Autodesk Fusion 360 part; units mm, degrees
(part 3 of 3)
extrude "Label 4.5 dot" cut sketch "Label 4.5 dot sketch" along normal blind 1 bodies 10 in component "07 Spar fit coupon - 4.1 4.3 4.4 4.5 4.7"
ref_plane "WorkPlane36" through (0, 0, 9.4) normal (0, 0, 1) x (1, 0, 0) in component "07 Spar fit coupon - 4.1 4.3 4.4 4.5 4.7"
sketch "Label 4.5 digit 2 a sketch" plane through (0, 0, 9.4) normal (0, 0, 1) x (1, 0, 0) in component "07 Spar fit coupon - 4.1 4.3 4.4 4.5 4.7"
  line L0 (13, 43.2) -> (14.8, 43.2)
  line L1 (14.8, 43.2) -> (14.8, 43.5)
  line L2 (14.8, 43.5) -> (13, 43.5)
  line L3 (13, 43.5) -> (13, 43.2)
extrude "Label 4.5 digit 2 a" cut sketch "Label 4.5 digit 2 a sketch" along normal blind 1 bodies 10 in component "07 Spar fit coupon - 4.1 4.3 4.4 4.5 4.7"
ref_plane "WorkPlane37" through (0, 0, 9.4) normal (0, 0, 1) x (1, 0, 0) in component "07 Spar fit coupon - 4.1 4.3 4.4 4.5 4.7"
sketch "Label 4.5 digit 2 f sketch" plane through (0, 0, 9.4) normal (0, 0, 1) x (1, 0, 0) in component "07 Spar fit coupon - 4.1 4.3 4.4 4.5 4.7"
  line L0 (13, 42.15) -> (13.3, 42.15)
  line L1 (13.3, 42.15) -> (13.3, 43.05)
  line L2 (13.3, 43.05) -> (13, 43.05)
  line L3 (13, 43.05) -> (13, 42.15)
extrude "Label 4.5 digit 2 f" cut sketch "Label 4.5 digit 2 f sketch" along normal blind 1 bodies 10 in component "07 Spar fit coupon - 4.1 4.3 4.4 4.5 4.7"
ref_plane "WorkPlane38" through (0, 0, 9.4) normal (0, 0, 1) x (1, 0, 0) in component "07 Spar fit coupon - 4.1 4.3 4.4 4.5 4.7"
sketch "Label 4.5 digit 2 g sketch" plane through (0, 0, 9.4) normal (0, 0, 1) x (1, 0, 0) in component "07 Spar fit coupon - 4.1 4.3 4.4 4.5 4.7"
  line L0 (13, 41.85) -> (14.8, 41.85)
  line L1 (14.8, 41.85) -> (14.8, 42.15)
  line L2 (14.8, 42.15) -> (13, 42.15)
  line L3 (13, 42.15) -> (13, 41.85)
extrude "Label 4.5 digit 2 g" cut sketch "Label 4.5 digit 2 g sketch" along normal blind 1 bodies 10 in component "07 Spar fit coupon - 4.1 4.3 4.4 4.5 4.7"
ref_plane "WorkPlane39" through (0, 0, 9.4) normal (0, 0, 1) x (1, 0, 0) in component "07 Spar fit coupon - 4.1 4.3 4.4 4.5 4.7"
sketch "Label 4.5 digit 2 c sketch" plane through (0, 0, 9.4) normal (0, 0, 1) x (1, 0, 0) in component "07 Spar fit coupon - 4.1 4.3 4.4 4.5 4.7"
  line L0 (14.5, 40.95) -> (14.8, 40.95)
  line L1 (14.8, 40.95) -> (14.8, 41.85)
  line L2 (14.8, 41.85) -> (14.5, 41.85)
  line L3 (14.5, 41.85) -> (14.5, 40.95)
extrude "Label 4.5 digit 2 c" cut sketch "Label 4.5 digit 2 c sketch" along normal blind 1 bodies 10 in component "07 Spar fit coupon - 4.1 4.3 4.4 4.5 4.7"
ref_plane "WorkPlane40" through (0, 0, 9.4) normal (0, 0, 1) x (1, 0, 0) in component "07 Spar fit coupon - 4.1 4.3 4.4 4.5 4.7"
sketch "Label 4.5 digit 2 d sketch" plane through (0, 0, 9.4) normal (0, 0, 1) x (1, 0, 0) in component "07 Spar fit coupon - 4.1 4.3 4.4 4.5 4.7"
  line L0 (13, 40.5) -> (14.8, 40.5)
  line L1 (14.8, 40.5) -> (14.8, 40.8)
  line L2 (14.8, 40.8) -> (13, 40.8)
  line L3 (13, 40.8) -> (13, 40.5)
extrude "Label 4.5 digit 2 d" cut sketch "Label 4.5 digit 2 d sketch" along normal blind 1 bodies 10 in component "07 Spar fit coupon - 4.1 4.3 4.4 4.5 4.7"
ref_plane "WorkPlane41" through (-0.05, 0, 0) normal (1, 0, 0) x (0, 1, 0) in component "07 Spar fit coupon - 4.1 4.3 4.4 4.5 4.7"
sketch "Diamond 4.7 mm flat-width fit bore sketch" plane through (-0.05, 0, 0) normal (1, 0, 0) x (0, 0, -1) in component "07 Spar fit coupon - 4.1 4.3 4.4 4.5 4.7"
  line L0 (-4.5, 50.6766) -> (-1.1766, 54)
  line L1 (-1.1766, 54) -> (-4.5, 57.3234)
  line L2 (-4.5, 57.3234) -> (-7.8234, 54)
  line L3 (-7.8234, 54) -> (-4.5, 50.6766)
extrude "Diamond 4.7 mm flat-width fit bore" cut sketch "Diamond 4.7 mm flat-width fit bore sketch" along normal blind 24.1 bodies 10 in component "07 Spar fit coupon - 4.1 4.3 4.4 4.5 4.7"
ref_plane "WorkPlane42" through (0, 0, 9.4) normal (0, 0, 1) x (1, 0, 0) in component "07 Spar fit coupon - 4.1 4.3 4.4 4.5 4.7"
sketch "Label 4.7 digit 0 f sketch" plane through (0, 0, 9.4) normal (0, 0, 1) x (1, 0, 0) in component "07 Spar fit coupon - 4.1 4.3 4.4 4.5 4.7"
  line L0 (8, 54.15) -> (8.3, 54.15)
  line L1 (8.3, 54.15) -> (8.3, 55.05)
  line L2 (8.3, 55.05) -> (8, 55.05)
  line L3 (8, 55.05) -> (8, 54.15)
extrude "Label 4.7 digit 0 f" cut sketch "Label 4.7 digit 0 f sketch" along normal blind 1 bodies 10 in component "07 Spar fit coupon - 4.1 4.3 4.4 4.5 4.7"
ref_plane "WorkPlane43" through (0, 0, 9.4) normal (0, 0, 1) x (1, 0, 0) in component "07 Spar fit coupon - 4.1 4.3 4.4 4.5 4.7"
sketch "Label 4.7 digit 0 g sketch" plane through (0, 0, 9.4) normal (0, 0, 1) x (1, 0, 0) in component "07 Spar fit coupon - 4.1 4.3 4.4 4.5 4.7"
  line L0 (8, 53.85) -> (9.8, 53.85)
  line L1 (9.8, 53.85) -> (9.8, 54.15)
  line L2 (9.8, 54.15) -> (8, 54.15)
  line L3 (8, 54.15) -> (8, 53.85)
extrude "Label 4.7 digit 0 g" cut sketch "Label 4.7 digit 0 g sketch" along normal blind 1 bodies 10 in component "07 Spar fit coupon - 4.1 4.3 4.4 4.5 4.7"
ref_plane "WorkPlane44" through (0, 0, 9.4) normal (0, 0, 1) x (1, 0, 0) in component "07 Spar fit coupon - 4.1 4.3 4.4 4.5 4.7"
sketch "Label 4.7 digit 0 b sketch" plane through (0, 0, 9.4) normal (0, 0, 1) x (1, 0, 0) in component "07 Spar fit coupon - 4.1 4.3 4.4 4.5 4.7"
  line L0 (9.5, 54.15) -> (9.8, 54.15)
  line L1 (9.8, 54.15) -> (9.8, 55.05)
  line L2 (9.8, 55.05) -> (9.5, 55.05)
  line L3 (9.5, 55.05) -> (9.5, 54.15)
extrude "Label 4.7 digit 0 b" cut sketch "Label 4.7 digit 0 b sketch" along normal blind 1 bodies 10 in component "07 Spar fit coupon - 4.1 4.3 4.4 4.5 4.7"
ref_plane "WorkPlane45" through (0, 0, 9.4) normal (0, 0, 1) x (1, 0, 0) in component "07 Spar fit coupon - 4.1 4.3 4.4 4.5 4.7"
sketch "Label 4.7 digit 0 c sketch" plane through (0, 0, 9.4) normal (0, 0, 1) x (1, 0, 0) in component "07 Spar fit coupon - 4.1 4.3 4.4 4.5 4.7"
  line L0 (9.5, 52.95) -> (9.8, 52.95)
  line L1 (9.8, 52.95) -> (9.8, 53.85)
  line L2 (9.8, 53.85) -> (9.5, 53.85)
  line L3 (9.5, 53.85) -> (9.5, 52.95)
extrude "Label 4.7 digit 0 c" cut sketch "Label 4.7 digit 0 c sketch" along normal blind 1 bodies 10 in component "07 Spar fit coupon - 4.1 4.3 4.4 4.5 4.7"
ref_plane "WorkPlane46" through (0, 0, 9.4) normal (0, 0, 1) x (1, 0, 0) in component "07 Spar fit coupon - 4.1 4.3 4.4 4.5 4.7"
sketch "Label 4.7 dot sketch" plane through (0, 0, 9.4) normal (0, 0, 1) x (1, 0, 0) in component "07 Spar fit coupon - 4.1 4.3 4.4 4.5 4.7"
  line L0 (10.5, 52.5) -> (10.85, 52.5)
  line L1 (10.85, 52.5) -> (10.85, 52.85)
  line L2 (10.85, 52.85) -> (10.5, 52.85)
  line L3 (10.5, 52.85) -> (10.5, 52.5)
extrude "Label 4.7 dot" cut sketch "Label 4.7 dot sketch" along normal blind 1 bodies 10 in component "07 Spar fit coupon - 4.1 4.3 4.4 4.5 4.7"
ref_plane "WorkPlane47" through (0, 0, 9.4) normal (0, 0, 1) x (1, 0, 0) in component "07 Spar fit coupon - 4.1 4.3 4.4 4.5 4.7"
sketch "Label 4.7 digit 2 a sketch" plane through (0, 0, 9.4) normal (0, 0, 1) x (1, 0, 0) in component "07 Spar fit coupon - 4.1 4.3 4.4 4.5 4.7"
  line L0 (13, 55.2) -> (14.8, 55.2)
  line L1 (14.8, 55.2) -> (14.8, 55.5)
  line L2 (14.8, 55.5) -> (13, 55.5)
  line L3 (13, 55.5) -> (13, 55.2)
extrude "Label 4.7 digit 2 a" cut sketch "Label 4.7 digit 2 a sketch" along normal blind 1 bodies 10 in component "07 Spar fit coupon - 4.1 4.3 4.4 4.5 4.7"
ref_plane "WorkPlane48" through (0, 0, 9.4) normal (0, 0, 1) x (1, 0, 0) in component "07 Spar fit coupon - 4.1 4.3 4.4 4.5 4.7"
sketch "Label 4.7 digit 2 b sketch" plane through (0, 0, 9.4) normal (0, 0, 1) x (1, 0, 0) in component "07 Spar fit coupon - 4.1 4.3 4.4 4.5 4.7"
  line L0 (14.5, 54.15) -> (14.8, 54.15)
  line L1 (14.8, 54.15) -> (14.8, 55.05)
  line L2 (14.8, 55.05) -> (14.5, 55.05)
  line L3 (14.5, 55.05) -> (14.5, 54.15)
extrude "Label 4.7 digit 2 b" cut sketch "Label 4.7 digit 2 b sketch" along normal blind 1 bodies 10 in component "07 Spar fit coupon - 4.1 4.3 4.4 4.5 4.7"
ref_plane "WorkPlane49" through (0, 0, 9.4) normal (0, 0, 1) x (1, 0, 0) in component "07 Spar fit coupon - 4.1 4.3 4.4 4.5 4.7"
sketch "Label 4.7 digit 2 c sketch" plane through (0, 0, 9.4) normal (0, 0, 1) x (1, 0, 0) in component "07 Spar fit coupon - 4.1 4.3 4.4 4.5 4.7"
  line L0 (14.5, 52.95) -> (14.8, 52.95)
  line L1 (14.8, 52.95) -> (14.8, 53.85)
  line L2 (14.8, 53.85) -> (14.5, 53.85)
  line L3 (14.5, 53.85) -> (14.5, 52.95)
extrude "Label 4.7 digit 2 c" cut sketch "Label 4.7 digit 2 c sketch" along normal blind 1 bodies 10 in component "07 Spar fit coupon - 4.1 4.3 4.4 4.5 4.7"
ref_plane "WorkPlane1" through (0, 0, 52.7) normal (0, 0, 1) x (1, 0, 0) in component "REFERENCE ONLY - bamboo, example bar cell, sensor envelopes"
sketch "EXAMPLE 60mm bar cell - no assumed screw pattern sketch" plane through (0, 0, 52.7) normal (0, 0, 1) x (1, 0, 0) in component "REFERENCE ONLY - bamboo, example bar cell, sensor envelopes"
  line L0 (368.4, -6.35) -> (428.4, -6.35)
  line L1 (428.4, -6.35) -> (428.4, 6.35)
  line L2 (428.4, 6.35) -> (368.4, 6.35)
  line L3 (368.4, 6.35) -> (368.4, -6.35)
extrude "EXAMPLE 60mm bar cell - no assumed screw pattern" add sketch "EXAMPLE 60mm bar cell - no assumed screw pattern sketch" along normal blind 12.7 separate body makes body 11 in component "REFERENCE ONLY - bamboo, example bar cell, sensor envelopes"
ref_plane "WorkPlane2" through (-6.6, 0, 0) normal (1, 0, 0) x (0, 1, 0) in component "REFERENCE ONLY - bamboo, example bar cell, sensor envelopes"
sketch "4mm bamboo reference -18 sketch" plane through (-6.6, 0, 0) normal (1, 0, 0) x (0, 0, -1) in component "REFERENCE ONLY - bamboo, example bar cell, sensor envelopes"
  circle A0 centre (-20.5, -18) radius 2
extrude "4mm bamboo reference -18" add sketch "4mm bamboo reference -18 sketch" along normal blind 361 separate body makes body 12 in component "REFERENCE ONLY - bamboo, example bar cell, sensor envelopes"
ref_plane "WorkPlane3" through (-6.6, 0, 0) normal (1, 0, 0) x (0, 1, 0) in component "REFERENCE ONLY - bamboo, example bar cell, sensor envelopes"
sketch "4mm bamboo reference 18 sketch" plane through (-6.6, 0, 0) normal (1, 0, 0) x (0, 0, -1) in component "REFERENCE ONLY - bamboo, example bar cell, sensor envelopes"
  circle A0 centre (-20.5, 18) radius 2
extrude "4mm bamboo reference 18" add sketch "4mm bamboo reference 18 sketch" along normal blind 361 separate body makes body 13 in component "REFERENCE ONLY - bamboo, example bar cell, sensor envelopes"
ref_plane "WorkPlane4" through (0, 0, 23.2) normal (0, 0, 1) x (1, 0, 0) in component "REFERENCE ONLY - bamboo, example bar cell, sensor envelopes"
sketch "MPU board envelope sketch" plane through (0, 0, 23.2) normal (0, 0, 1) x (1, 0, 0) in component "REFERENCE ONLY - bamboo, example bar cell, sensor envelopes"
  line L0 (75, -10) -> (97, -10)
  line L1 (97, -10) -> (97, 10)
  line L2 (97, 10) -> (75, 10)
  line L3 (75, 10) -> (75, -10)
extrude "MPU board envelope" add sketch "MPU board envelope sketch" along normal blind 1.6 separate body makes body 14 in component "REFERENCE ONLY - bamboo, example bar cell, sensor envelopes"
ref_plane "WorkPlane5" through (0, 0, 17.8) normal (0, 0, 1) x (1, 0, 0) in component "REFERENCE ONLY - bamboo, example bar cell, sensor envelopes"
sketch "Gauge backing envelope sketch" plane through (0, 0, 17.8) normal (0, 0, 1) x (1, 0, 0) in component "REFERENCE ONLY - bamboo, example bar cell, sensor envelopes"
  line L0 (33, -3) -> (43, -3)
  line L1 (43, -3) -> (43, 3)
  line L2 (43, 3) -> (33, 3)
  line L3 (33, 3) -> (33, -3)
extrude "Gauge backing envelope" add sketch "Gauge backing envelope sketch" along normal blind 0.2 separate body makes body 15 in component "REFERENCE ONLY - bamboo, example bar cell, sensor envelopes"
component "01A Wing root - gauge and MPU" placed x (1, 0, 0) y (0, 1, 0) z (0, 0, 1) at (0, 0, 16)
component "01B Wing middle" placed x (1, 0, 0) y (0, 1, 0) z (0, 0, 1) at (128.2, 0, 16)
component "01C Wing tip - load adapter" placed x (1, 0, 0) y (0, 1, 0) z (0, 0, 1) at (242.4, 0, 16)
component "07 Joint sandwich plate - print FOUR" placed x (1, 0, 0) y (0, 1, 0) z (0, 0, 1) at (116, 0, 14)
component "02 Root base - bench clamp" placed x (1, 0, 0) y (0, 1, 0) z (0, 0, 1) at (0, 0, 0)
component "03 Root cap" placed x (1, 0, 0) y (0, 1, 0) z (0, 0, 1) at (0, 0, 26)
component "04 Tip adapter - adjustable glue mount rails" placed x (1, 0, 0) y (0, 1, 0) z (0, 0, 1) at (340.4, 0, 25)
component "05 Fixed end glue pedestal" placed x (1, 0, 0) y (0, 1, 0) z (0, 0, 1) at (373.4, 0, 31)
component "06 Free end glue hanger" placed x (1, 0, 0) y (0, 1, 0) z (0, 0, 1) at (423.4, 0, 41)
component "07 Spar fit coupon - 4.1 4.3 4.4 4.5 4.7" placed x (1, 0, 0) y (0, 1, 0) z (0, 0, 1) at (-65, 85, 0)
component "07 Joint sandwich plate - print FOUR" placed x (1, 0, 0) y (0, 1, 0) z (0, 0, 1) at (116, 0, 18.4)
component "07 Joint sandwich plate - print FOUR" placed x (1, 0, 0) y (0, 1, 0) z (0, 0, 1) at (230.2, 0, 14)
component "07 Joint sandwich plate - print FOUR" placed x (1, 0, 0) y (0, 1, 0) z (0, 0, 1) at (230.2, 0, 18.4)
component "REFERENCE ONLY - bamboo, example bar cell, sensor envelopes" placed x (1, 0, 0) y (0, 1, 0) z (0, 0, 1) at (0, 0, 0)
equation "sparDiameter = 4 mm" comment "Nominal bamboo diameter; choose clearance with fit coupon"
equation "sparClearance = 0.5 mm" comment "Diametral clearance; 4.5 mm coupon fit selected by user"
equation "sparBore = sparDiameter + sparClearance" comment "Flat-to-flat width of all six native diamond passages"
equation "m3Clearance = 3.4 mm" comment "Root registration and tip adapter holes"
equation "m4Clearance = 4.4 mm" comment "Root clamp bolt holes"
equation "rootThickness = 10 mm" comment "Root tongue extrusion; reposition cap if changed"
equation "gaugeBeamThickness = 1.8 mm" comment "Root gauge zone; physical response needs testing"
equation "spanStripThickness = 2.4 mm" comment "Middle, tip and reinforced joint-end thickness"
equation "mpuPadThickness = 7.2 mm" comment "Raised pad clears the 6.95 mm rib tops"
equation "d10 = gaugeBeamThickness"
equation "d12 = rootThickness"
equation "d14 = spanStripThickness"
equation "d98 = spanStripThickness"
equation "d102 = m3Clearance"
equation "d105 = mpuPadThickness"
equation "d109 = m3Clearance"
equation "d114 = m3Clearance"
equation "d135 = sparBore * sqrt(2)"
equation "d140 = sparBore * sqrt(2)"
equation "d143 = spanStripThickness"
equation "d225 = spanStripThickness"
equation "d229 = m3Clearance"
equation "d232 = spanStripThickness"
equation "d236 = m3Clearance"
equation "d241 = sparBore * sqrt(2)"
equation "d246 = sparBore * sqrt(2)"
equation "d249 = spanStripThickness"
equation "d315 = spanStripThickness"
equation "d319 = m3Clearance"
equation "d328 = m3Clearance"
equation "d333 = m3Clearance"
equation "d338 = m3Clearance"
equation "d343 = m3Clearance"
equation "d348 = sparBore * sqrt(2)"
equation "d353 = sparBore * sqrt(2)"
equation "d360 = m3Clearance"
equation "d365 = m3Clearance"
equation "d384 = m4Clearance"
equation "d393 = m4Clearance"
equation "d402 = m4Clearance"
equation "d411 = m4Clearance"
equation "d430 = m4Clearance"
equation "d435 = m4Clearance"
equation "d440 = m4Clearance"
equation "d445 = m4Clearance"
equation "d452 = m3Clearance"
equation "d457 = m3Clearance"
equation "d462 = m3Clearance"
equation "d467 = m3Clearance"
equation "d506 = m3Clearance"
equation "d511 = m3Clearance"
equation "d516 = m3Clearance"
equation "d521 = m3Clearance"
named bodies: "wing_root - printable solid", "wing_middle - printable solid", "wing_tip - printable solid", "joint_plate - printable solid", "root_base - printable solid", "root_cap - printable solid", "tip_adapter - printable solid", "cell_spacer - printable solid", "load_hanger - printable solid", "spar_fit_coupon - printable solid"
